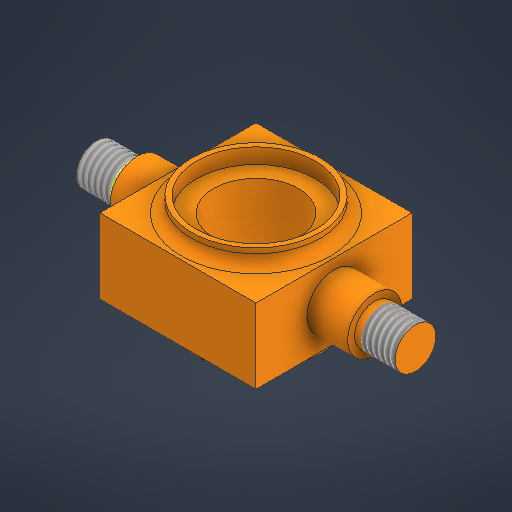
# Autodesk Inventor part: 3.hook ancor
Saved by Autodesk Inventor 2026.1 (Build 301233020, 233B)
## iProperties
Created: 2026-01-20
Part Number: 3.hook ancor
Material: Steel, Mild
Document SubType Name: Modeling
Designer: anith
Density: 7.85 g/cm^3
Appearance: Semi-Polished
Author: anith
Autodesk Inventor part; units mm, degrees
ref_plane "YZ Plane" through (0, 0, 0) normal (1, 0, 0) x (0, 1, 0)
ref_plane "XZ Plane" through (0, 0, 0) normal (0, 1, 0) x (-1, 0, 0)
ref_plane "XY Plane" through (0, 0, 0) normal (0, 0, 1) x (1, 0, 0)
sketch "Sketch1" plane through (0, 0, 0) normal (0, 1, 0) x (-1, 0, 0)
  line L0 (23, 11) -> (-23, 11)
  line L1 (-23, 11) -> (-23, -11)
  line L2 (-23, -11) -> (23, -11)
  line L3 (23, -11) -> (23, 11)
  line L4 (23, 11) -> (-23, -11) construction
  line L5 (-23, 11) -> (23, -11) construction
  point P0 (0, 0)
  dimension "d0" = 46
  dimension "d1" = 22
  constraints: 12 end point, 2 midpoint, 2 parallel, 1 horizontal, 1 perpendicular
  measures "d0" distance of L2.end L1.end
  measures "d1" distance of L1.end L0.end
extrude "Extrusion1" add sketch "Sketch1" along normal blind 46
sketch "Sketch2" plane through (23, 0, 11) normal (1, 0, 0) x (0, 0, -1)
  line L0 (0, 0) -> (22, 0) projected
  line L1 (22, 0) -> (22, 46) projected
  line L2 (0, 46) -> (22, 46) projected
  line L3 (0, 0) -> (0, 46) projected
  circle A0 centre (11, 23) radius 8
  point P0 (11, 0)
  dimension "d4" = 16
  dimension "d5" = 23
  dimension "d6" = 11
  constraints: 1 centre point
  measures "d4" diameter of A0
  measures "d5" distance from line of L0 A0.centre
  measures "d6" distance from line of L3 A0.centre
extrude "Extrusion2" add sketch "Sketch2" along normal blind 12 contours A0
sketch "Sketch3" plane through (35, 23, 0) normal (1, 0, 0) x (0, 0, -1)
  circle A0 centre (0, 0) radius 6
  circle A1 centre (0, 0) radius 8 projected
  point P0 (0, -23)
  dimension "d9" = 12
  dimension "d10" = 23
  dimension "d11" = 0
  constraints: 1 centre point
  measures "d9" diameter of A0
  measures "d10" distance of A0.centre point (0, -23)
  measures "d11" distance of A1.centre A0.centre
extrude "Extrusion3" add sketch "Sketch3" along normal blind 12 contours A0
thread "Thread1" size "M12x1.75" class "6g" standard "ANSI Metric M Profile" length 12 offset 2
sketch "Sketch4" plane through (-23, 0, -11) normal (-1, 0, 0) x (0, 0, 1)
  line L0 (0, 0) -> (22, 0) projected
  line L1 (22, 0) -> (22, 46) projected
  line L2 (0, 46) -> (22, 46) projected
  line L3 (0, 0) -> (0, 46) projected
  circle A0 centre (11, 23) radius 8
  point P0 (11, 0)
  dimension "d16" = 16
  dimension "d17" = 11
  dimension "d18" = 23
  constraints: 1 centre point
  measures "d16" diameter of A0
  measures "d17" distance from line of L1 A0.centre
  measures "d18" distance from line of L2 A0.centre
extrude "Extrusion4" add sketch "Sketch4" along normal blind 12 contours A0
sketch "Sketch5" plane through (-35, 23, 0) normal (-1, 0, 0) x (0, 0, 1)
  circle A0 centre (0, 0) radius 6
  circle A1 centre (0, 0) radius 8 projected
  line L0 (-11, -23) -> (11, -23) projected
  line L1 (11, -23) -> (11, 23) projected
  line L2 (-11, 23) -> (11, 23) projected
  line L3 (-11, -23) -> (-11, 23) projected
  point P0 (0, -23)
  dimension "d21" = 12
  dimension "d22" = 23
  dimension "d23" = 11
  constraints: 1 centre point
  measures "d21" diameter of A0
  measures "d22" distance of A0.centre point (0, -23)
  measures "d23" distance from line of L3 A0.centre
extrude "Extrusion5" add sketch "Sketch5" along normal blind 12 contours A0
thread "Thread2" size "M12x1.75" class "6g" standard "ANSI Metric M Profile" length 12 offset 2
sketch "Sketch6" plane through (-23, 0, 11) normal (0, 0, 1) x (1, 0, 0)
  line L0 (0, 0) -> (46, 0) projected
  line L1 (46, 0) -> (46, 46) projected
  line L2 (0, 46) -> (46, 46) projected
  line L3 (0, 0) -> (0, 46) projected
  circle A0 centre (23, 23) radius 19
  circle A1 centre (23, 23) radius 17.5
  circle A2 centre (23, 23) radius 12.5
  point P0 (23, 0)
  point P1 (46, 23)
  dimension "d28" = 38
  dimension "d29" = 35
  dimension "d30" = 23
  dimension "d31" = 23
  dimension "d32" = 25
  constraints: 3 centre point, 2 coincident, 1 midpoint
  measures "d28" diameter of A0
  measures "d29" diameter of A1
  measures "d30" distance from line of L2 A0.centre
  measures "d31" distance of point (46, 23) A0.centre
  measures "d32" diameter of A2
extrude "Extrusion6" add sketch "Sketch6" along normal blind 4.5 contours A0
fillet "Fillet1" radius 3 1 edges at (-19, 23, 11)
extrude "Extrusion7" cut sketch "Sketch6" against normal through all contours A2
sketch "Sketch7" plane through (23, 0, -11) normal (0, 0, -1) x (-1, 0, 0)
  circle A0 centre (23, 23) radius 19
  circle A1 centre (23, 23) radius 17.5
  line L0 (46, 0) -> (46, 46) projected
  line L1 (0, 0) -> (46, 0) projected
  point P0 (23, 0)
  dimension "d38" = 38
  dimension "d39" = 35
  dimension "d40" = 23
  dimension "d41" = 23
  constraints: 2 centre point, 1 coincident
  measures "d38" diameter of A0
  measures "d39" diameter of A1
  measures "d40" distance from line of L0 A0.centre
  measures "d41" distance from line of L1 A0.centre
extrude "Extrusion8" add sketch "Sketch7" along normal blind 4.5
fillet "Fillet2" radius 3 1 edges at (19, 23, -11)
body "Solid1"
